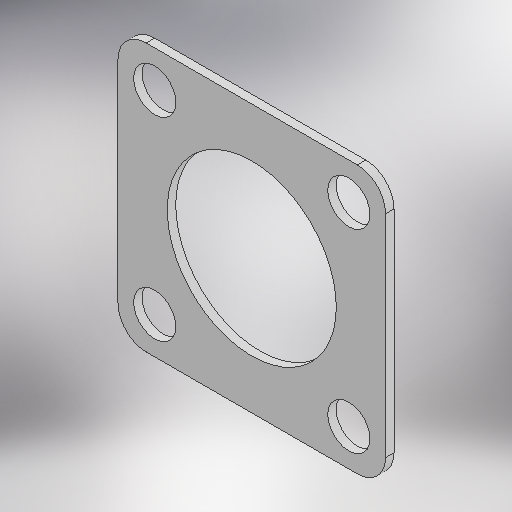
# Autodesk Inventor part: 3D_M2.5-space
Saved by Autodesk Inventor 2025.3 (Build 293356030, 356C)
## iProperties
Created: 2026-06-12
Part Number: 3D_M2.5-space
Material: 一般
Document SubType Name: Modeling
Designer: ibuki_ono
Density: 1 g/cm^3
Appearance: 既定
Author: ibuki_ono
## iProperties of the stored document 3D_M2.5-space_3D プリント.ipt
Created: 2026-06-12
Part Number: 3D_M2.5-space_3D プリント
Material: 一般
Document SubType Name: Modeling
Designer: ibuki_ono
Density: 1 g/cm^3
Appearance: 既定
Author: ibuki_ono
Autodesk Inventor part; units mm, degrees
ref_plane "YZ Plane" through (0, 0, 0) normal (1, 0, 0) x (0, 1, 0)
ref_plane "XZ Plane" through (0, 0, 0) normal (0, 1, 0) x (-1, 0, 0)
ref_plane "XY Plane" through (0, 0, 0) normal (0, 0, 1) x (1, 0, 0)
sketch "スケッチ1" plane through (0, 0, 0) normal (0, 0, 1) x (1, 0, 0)
  line L0 (-9.5, -9.5) -> (9.5, -9.5)
  line L1 (9.5, -9.5) -> (9.5, 9.5)
  line L2 (9.5, 9.5) -> (-9.5, 9.5)
  line L3 (-9.5, 9.5) -> (-9.5, -9.5)
  line L4 (-9.5, -9.5) -> (9.5, 9.5) construction
  line L5 (9.5, -9.5) -> (-9.5, 9.5) construction
  point P0 (0, 0)
  dimension "d0" = 19
  dimension "d1" = 19
  constraints: 12 end point, 2 midpoint, 2 parallel, 1 horizontal, 1 perpendicular
  measures "d0" distance of L2.end L1.end
  measures "d1" distance of L1.end L0.end
extrude "押し出し1" add sketch "スケッチ1" along normal blind 0.6
sketch "スケッチ2" plane through (0, 0, 0.6) normal (0, 0, 1) x (1, 0, 0)
  circle A0 centre (0, 0) radius 9.75 construction
  line L0 (-6.8943, -6.8943) -> (6.8943, -6.8943) construction
  line L1 (6.8943, -6.8943) -> (6.8943, 6.8943) construction
  line L2 (6.8943, 6.8943) -> (-6.8943, 6.8943) construction
  line L3 (-6.8943, 6.8943) -> (-6.8943, -6.8943) construction
  line L4 (-6.8943, -6.8943) -> (6.8943, 6.8943) construction
  line L5 (6.8943, -6.8943) -> (-6.8943, 6.8943) construction
  dimension "d4" = 19.5
  constraints: 12 end point, 5 coincident, 2 midpoint, 2 parallel, 2 perpendicular, 1 horizontal, 3 other
hole "穴1" at (-6.8943, 6.8943, 0.6) at (6.8943, 6.8943, 0.6) at (6.8943, -6.8943, 0.6) at (-6.8943, -6.8943, 0.6) direction (0, 0, -1) diameter 3 depth 4.4
sketch "スケッチ3" plane through (0, 0, 0.6) normal (0, 0, 1) x (1, 0, 0)
  circle A0 centre (0, 0) radius 6
  dimension "d12" = 12
  constraints: 1 centre point, 1 coincident
  measures "d12" diameter of A0
extrude "押し出し2" cut sketch "スケッチ3" against normal through all
fillet "フィレット1" radius 2 4 edges at (-9.5, 9.5, 0.3) (9.5, 9.5, 0.3) (9.5, -9.5, 0.3) (-9.5, -9.5, 0.3)
